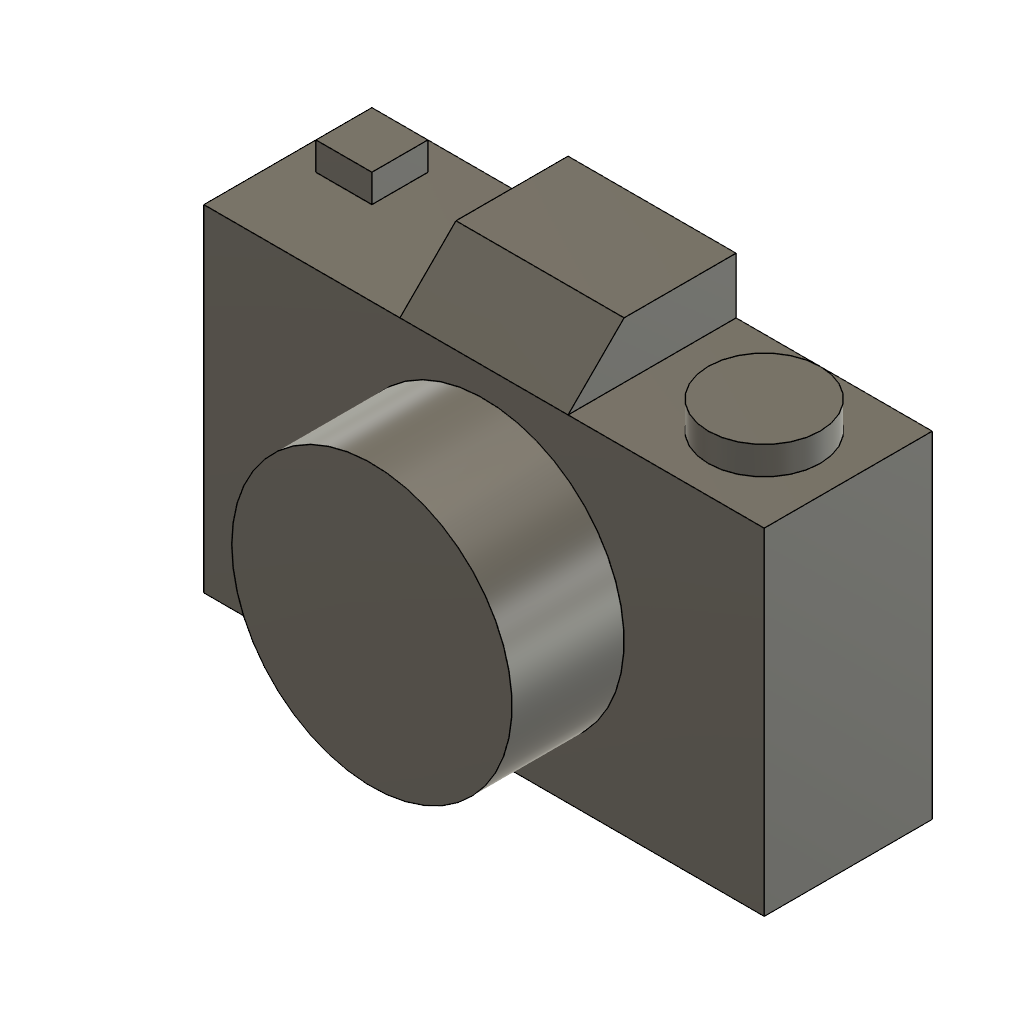
Camera (Autodesk Fusion 360 design; units mm, degrees)
part number: 2026-10-10-15-01-16-160
Autodesk Fusion 360 part; units mm, degrees
sketch "Sketch1" plane through (0, 0, 0) normal (0, 0, 1) x (1, 0, 0)
  line L0 (50, -30) -> (-50, -30)
  line L1 (-50, -30) -> (-50, 30)
  line L2 (-50, 30) -> (50, 30)
  line L3 (50, 30) -> (50, -30)
  line L4 (50, -30) -> (-50, 30) construction
  line L5 (-50, -30) -> (50, 30) construction
  dimension "d1" = 100
  dimension "d2" = 60
  constraint horizontal L0
  constraint perpendicular L0 L1
  constraint parallel L0 L2
  constraint parallel L1 L3
  constraint coincident L4 origin
  constraint coincident L5 origin
  measures "d1" distance of L1.end L2.end
  measures "d2" distance of L0.end L1.end
extrude "Extrude1" add sketch "Sketch1" along normal blind 30
sketch "Sketch2" plane through (0, 0, 30) normal (0, 0, 1) x (1, 0, 0)
  line L0 (50, 30) -> (-50, 30)
  line L1 (-50, 30) -> (-50, -30)
  line L2 (-50, -30) -> (50, -30)
  line L3 (50, -30) -> (50, 30)
  circle A0 centre (0, 0) radius 25
  dimension "d5" = 50
  constraint coincident A0.centre origin
  measures "d5" diameter of A0
extrude "Extrude2" add sketch "Sketch2" along normal blind 20 contours A0
sketch "Sketch3" plane through (0, 30, 0) normal (0, 1, 0) x (-1, 0, 0)
  line L0 (-50, 0) -> (50, 0)
  line L1 (50, 0) -> (50, 30)
  line L2 (50, 30) -> (-50, 30)
  line L3 (-50, 30) -> (-50, 0)
  line L4 (45, 5) -> (35, 5)
  line L5 (35, 5) -> (35, 15)
  line L6 (35, 15) -> (45, 15)
  line L7 (45, 15) -> (45, 5)
  circle A0 centre (-35, 15) radius 10
  dimension "d8" = 20
  dimension "d9" = 15
  dimension "d10" = 10
  dimension "d11" = 10
  dimension "d12" = 15
  dimension "d13" = 15
  dimension "d14" = 15
  constraint horizontal L4
  constraint vertical L5
  constraint horizontal L6
  constraint vertical L7
  measures "d8" diameter of A0
  measures "d9" distance of L1 L5
  measures "d10" distance of L4.start L4.end
  measures "d11" distance of L4.start L6.end
  measures "d12" distance of L0 L6
  measures "d13" distance of L0 A0.centre
  measures "d14" distance of L3 A0.centre
extrude "Extrude3" add sketch "Sketch3" along normal blind 5 contours L4 L5 L6 L7 | A0
sketch "Sketch4" plane through (0, 0, 0) normal (0, 0, -1) x (-1, 0, 0)
  line L0 (50, 30) -> (-50, 30)
  line L1 (-50, 30) -> (-50, -30)
  line L2 (-50, -30) -> (50, -30)
  line L3 (50, -30) -> (50, 30)
  line L4 (-15, 30) -> (15, 30)
  line L5 (15, 30) -> (15, 40)
  line L6 (15, 40) -> (-15, 40)
  line L7 (-15, 40) -> (-15, 30)
  dimension "d17" = 30
  dimension "d18" = 35
  dimension "d19" = 10
  constraint horizontal L4
  constraint vertical L5
  constraint horizontal L6
  constraint vertical L7
  constraint coincident L0 L4.start
  measures "d17" distance of L4.start L4.end
  measures "d18" distance of L3 L5
  measures "d19" distance of L4.start L6.end
extrude "Extrude4" add sketch "Sketch4" against normal blind 20 contours L0 L4 L5 L6 L7
sketch "Sketch5" plane through (15, 0, 0) normal (1, 0, 0) x (0, 0, -1)
  line L0 (0, 30) -> (0, 40)
  line L1 (0, 40) -> (-20, 40)
  line L2 (-20, 40) -> (-20, 30)
  line L3 (-20, 30) -> (0, 30)
  line L4 (-20, 40) -> (-30, 30)
  line L5 (-30, 30) -> (-19, 30)
  line L6 (-20, 40) -> (-20, 30)
  constraint coincident L1.end L2.start
  constraint coincident L3 L5.end
  constraint coincident L2.end L3.start
  constraint perpendicular L5 L6
extrude "Extrude5" add sketch "Sketch5" against normal blind 30 contours L2 L4 L5 L6
